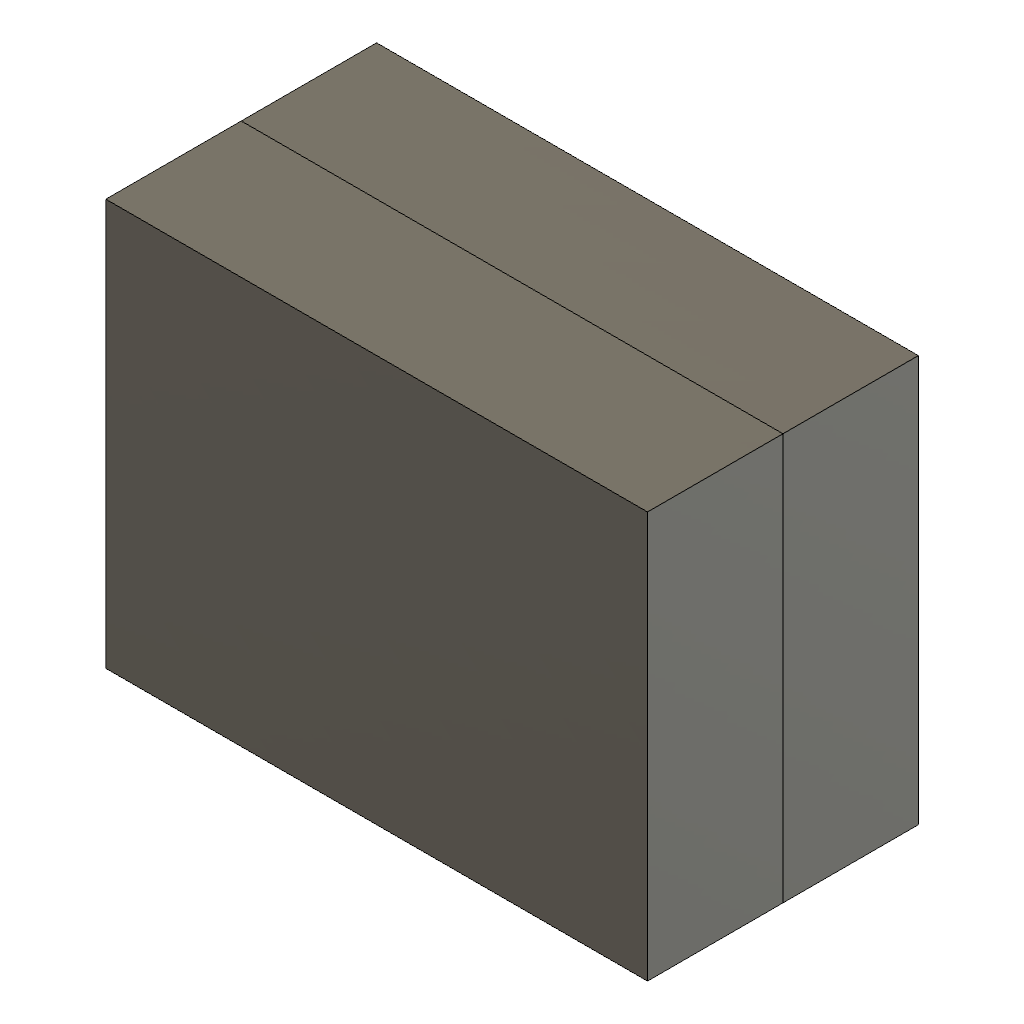
small_sheet_face_extend (Autodesk Fusion 360 design; units mm, degrees)
part number: 2026-10-21-16-14-23-663
Autodesk Fusion 360 part; units mm, degrees
sketch "OwnedSplitBlockProfile_small_sheet_face_extend" plane through (0, 0, 0) normal (0, 0, 1) x (1, 0, 0)
  line L0 (0, 0) -> (40, 0)
  line L1 (40, 0) -> (40, 30)
  line L2 (40, 30) -> (0, 30)
  line L3 (0, 30) -> (0, 0)
extrude "OwnedSplitBlockExtrude_small_sheet_face_extend" add sketch "OwnedSplitBlockProfile_small_sheet_face_extend" along normal blind 20 makes body 1
ref_plane "WorkPlane1" through (0, 0, 10) normal (0, 0, 1) x (1, 0, 0)
sketch "OwnedSplitPatchBoundary_small_sheet_face_extend" plane through (0, 0, 10) normal (0, 0, 1) x (1, 0, 0)
  line L0 (10, 10) -> (30, 10)
  line L1 (30, 10) -> (30, 20)
  line L2 (30, 20) -> (10, 20)
  line L3 (10, 20) -> (10, 10)
surface "OwnedSplitToolPatch_small_sheet_face_extend" add patch profiles "OwnedSplitPatchBoundary_small_sheet_face_extend" section 1 separate body makes body 2
split "OwnedSplitBodySheet_small_sheet_face_extend" by plane through (0, 0, 10) normal (0, 0, 1) bodies 1 makes body 3 at (13.3333, 20, 20)
named bodies: "OwnedSplitBlock_small_sheet_face_extend", "OwnedSplitToolSheet_small_sheet_face_extend", "OwnedSplitBlock_small_sheet_face_extend (1)"
